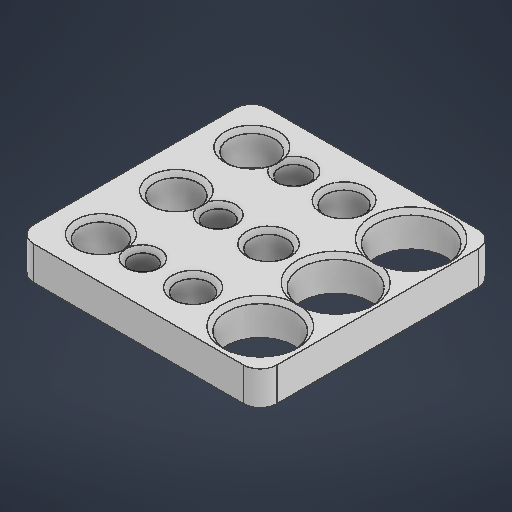
# Autodesk Inventor part: hole_test
Saved by Autodesk Inventor 2026.2 (Build 302298010, 298A)
## iProperties
Created: 2026-04-06
Part Number: hole_test
Material: 일반
Document SubType Name: Modeling
Designer: work
Density: 1 g/cm^3
Appearance: 기본값
Author: work
Autodesk Inventor part; units mm, degrees
ref_plane "YZ Plane" through (0, 0, 0) normal (1, 0, 0) x (0, 1, 0)
ref_plane "XZ Plane" through (0, 0, 0) normal (0, 1, 0) x (-1, 0, 0)
ref_plane "XY Plane" through (0, 0, 0) normal (0, 0, 1) x (1, 0, 0)
sketch "스케치1" plane through (0, 0, 0) normal (0, 1, 0) x (-1, 0, 0)
  circle A0 centre (0, 0) radius 4
  circle A1 centre (0, -9) radius 4.1
  circle A2 centre (0, -18) radius 4.2
  circle A3 centre (8, 0) radius 2
  circle A4 centre (8, -9) radius 2.1
  circle A5 centre (8, -18) radius 2.2
  circle A6 centre (14, 0) radius 1.5
  circle A7 centre (14, -9) radius 1.6
  circle A8 centre (14, -18) radius 1.7
  circle A9 centre (19, 0) radius 2.5
  circle A10 centre (19, -9) radius 2.6
  circle A11 centre (19, -18) radius 2.7
  line L0 (19, 0) -> (0, 0) construction
  line L1 (0, 0) -> (0, -18) construction
  line L2 (0, -18) -> (19, -18) construction
  line L3 (19, -18) -> (19, 0) construction
  line L4 (19, -9) -> (0, -9) construction
  line L5 (8, 0) -> (8, -18) construction
  line L6 (14, -18) -> (14, 0) construction
  line L7 (24, 5) -> (-5, 5)
  line L8 (-5, 5) -> (-5, -23)
  line L9 (-5, -23) -> (24, -23)
  line L10 (24, -23) -> (24, 5)
  dimension "d0" = 8
  dimension "d1" = 8.2
  dimension "d2" = 8.4
  dimension "d3" = 4
  dimension "d4" = 4.2
  dimension "d5" = 4.4
  dimension "d6" = 3
  dimension "d7" = 3.2
  dimension "d8" = 3.4
  dimension "d9" = 5
  dimension "d10" = 5.2
  dimension "d11" = 5.4
  dimension "d12" = 8
  dimension "d13" = 6
  dimension "d14" = 5
  dimension "d15" = 9
  dimension "d16" = 9
  dimension "d17" = 5
  dimension "d18" = 5
  dimension "d19" = 5
  dimension "d20" = 5
  constraints: 22 end point, 12 centre point, 5 perpendicular, 4 midpoint, 3 horizontal, 2 coincident, 2 parallel, 2 point on line, 1 vertical
  measures "d0" diameter of A0
  measures "d1" diameter of A1
  measures "d2" diameter of A2
  measures "d3" diameter of A3
  measures "d4" diameter of A4
  measures "d5" diameter of A5
  measures "d6" diameter of A6
  measures "d7" diameter of A7
  measures "d8" diameter of A8
  measures "d9" diameter of A9
  measures "d10" diameter of A10
  measures "d11" diameter of A11
  measures "d12" distance between parallel lines of L1 L5
  measures "d13" distance between parallel lines of L6 L5
  measures "d14" distance between parallel lines of L3 L6
  measures "d15" distance between parallel lines of L0 L4
  measures "d16" distance between parallel lines of L2 L4
  measures "d17" distance from line of L7 L0.end
  measures "d18" distance from line of L8 point (0, 0)
  measures "d19" distance from line of L9 L2.end
  measures "d20" distance from line of L4.start L10
extrude "돌출1" add sketch "스케치1" along normal blind 4
chamfer "모따기1" distance 0.5 angle 45 12 edges at (-16.5, 4, 0) (-12.5, 4, 0) (-6, 4, 0) (4, 4, 0) (-5.9, 4, -9) (-12.4, 4, -9) (-16.4, 4, -9) (-16.3, 4, -18) (-12.3, 4, -18) (-5.8, 4, -18) (4.2, 4, -18) (4.1, 4, -9)
fillet "모깎기1" radius 2 4 edges at (-24, 2, 5) (5, 2, 5) (5, 2, -23) (-24, 2, -23)
